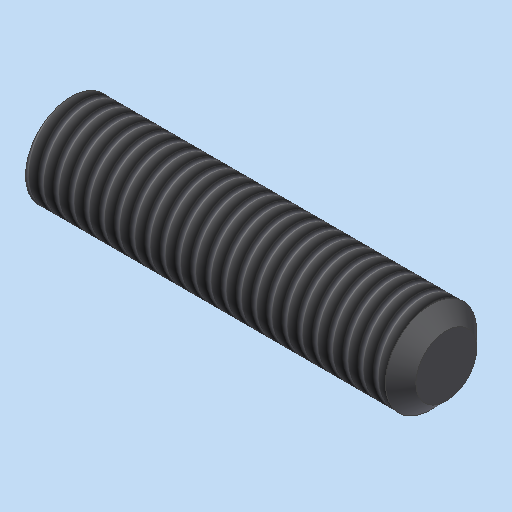
# Autodesk Inventor part: Gewindestift_DIN_913___M6x25
Saved by Autodesk Inventor 2023.3 (Build 273359000, 359)
## iProperties
Shininess: 64.0
Length Units: 11269
Angle Units: 11279
Time Units: 11290
Mass Units: 11283
Length Display Precision: 3
Angle Display Precision: 2
Compacted: True
Part Number: Gewindestift_DIN_913___M6x25
Document SubType Name: Modeling
Created: 2004-03-23
Material: xStahl_AnP_Dummymaterial
Description: =<RBPARTNOTITLE2>
Vendor: NORM8
Designer: S.Riedelsheimer
Manufacturer: Standard
Standards Organization: Custom
Density: 7.85 g/cm^3
Mass: 5.25327 g
Surface Area: 5.46085 cm^2
Volume: 0.669206 cm^3
Appearance: Stahl - normal AnP
Density: 0.0
Volumn: 0.0
Area: 0.0
PropertySet Name: Model Information
Control State: 0
Master: False
Checked Out: False
CNS_NB: Gewindestift DIN 913 - M6x25
CNS_NN: DIN 913
CNS_NT: Gewindestift mit Innensechskant und Kegelkuppe
CNS_NBSYN: Gewindestift DIN 913 - $NENN.
CNS_LINA: Gewindestift DIN 913 - M6x25
CNS_NENN: M6x25
CNS_D: 6.000
CNS_D3: 4.773
CNS_P: 1.000
CNS_L: 25.000
CNS_DP: 4.000
CNS_S: 3.000
CNS_T: 3.500
CNS_KT: X
PSOL_IDENT_0: {C:\partsolutions8\data\23d-libs\bosch_bamberg\schrauben\gewindestifte\din_913.prj},164 {M=Nenngewin
PSOL_IDENT_1: de},{VTYP=3D},{NB=Gewindestift DIN 913 - M6x25},{NN=DIN 913},{DATE=26.11.2003},{GEOMDATE=26.11.2003}
PSOL_IDENT_2: ,{VERSION=v1},{LINEID=540},{LINESUBID=-1},{WBVAR=}  {NB=Gewindestift DIN 913 - M6x25},{LINA=Gewindes
PSOL_IDENT_3: tift DIN 913 - M6x25},{KT=X},{IDNR=},{NENN=M6x25},{D=6.000},{D3=4.773},{P=1.000},{L=25.000},{DP=4.00
PSOL_IDENT_4: 0},{S=3.000},{T=3.500}
RBDRAWINGMISSINGSPEC: --
RBPARTNOTITLE2: Gewindestifte mit Innensechskant mit Kegelstumpf
AnP_Kategorie: 5
RBPARTNOTITLE1: Hexagon socket set screws with flat point
RBPARTMADEOF: DIN 913 - M6x25 - 8.8 - verzinkt
Title: Gewindestift DIN 913 - M6x25
Author: S.Riedelsheimer
Keywords: =<RBPARTMADEOF>
Comments: =<RBSURFACE2>
Revision Number: 01
Autodesk Inventor part; units mm, degrees
sketch "Sketch_1" plane through (0, 0, 0) normal (0, 0, 1) x (1, 0, 0)
  line L0 (1, 0) -> (25, 0)
  line L1 (25, 0) -> (25, -2)
  line L2 (25, -2) -> (24, -3)
  line L3 (24, -3) -> (0.3542, -3)
  line L4 (0.3542, -3) -> (0, -2.3865)
  line L5 (0, -2.3865) -> (0, -1.7321)
  line L6 (0, -1.7321) -> (1, 0)
  line L7 (1, 0) -> (25, 0)
  constraints: 16 end point
revolve "Drehung1" add sketch "Sketch_1" angle 360 about axis through (1, 0, 0) along (1, 0, 0)
thread "Gewinde1" size "M6x1" class "6g" standard "ANSI Metric M Profile" length 24.6135
sketch "Sketch_2" plane through (0, 0, 0) normal (1, 0, 0) x (0, 1, 0)
  line L0 (0, 1.7321) -> (-1.5, 0.866)
  line L1 (-1.5, 0.866) -> (-1.5, -0.866)
  line L2 (-1.5, -0.866) -> (0, -1.7321)
  line L3 (0, -1.7321) -> (1.5, -0.866)
  line L4 (1.5, -0.866) -> (1.5, 0.866)
  line L5 (1.5, 0.866) -> (0, 1.7321)
  constraints: 12 end point
extrude "Extrusion1" cut sketch "Sketch_2" along normal blind 3.5
ref_plane "IP1_XY" through (0, 0, 0) normal (1, 0, 0) x (0, 0, -1)
ref_plane "IP1_YZ" through (0, 0, 0) normal (0, 0, -1) x (0, 1, 0)
ref_plane "IP2_XY" through (25, 0, 0) normal (1, 0, 0) x (0, 0, -1)
ref_plane "IP2_YZ" through (25, 0, 0) normal (0, 0, -1) x (0, 1, 0)
